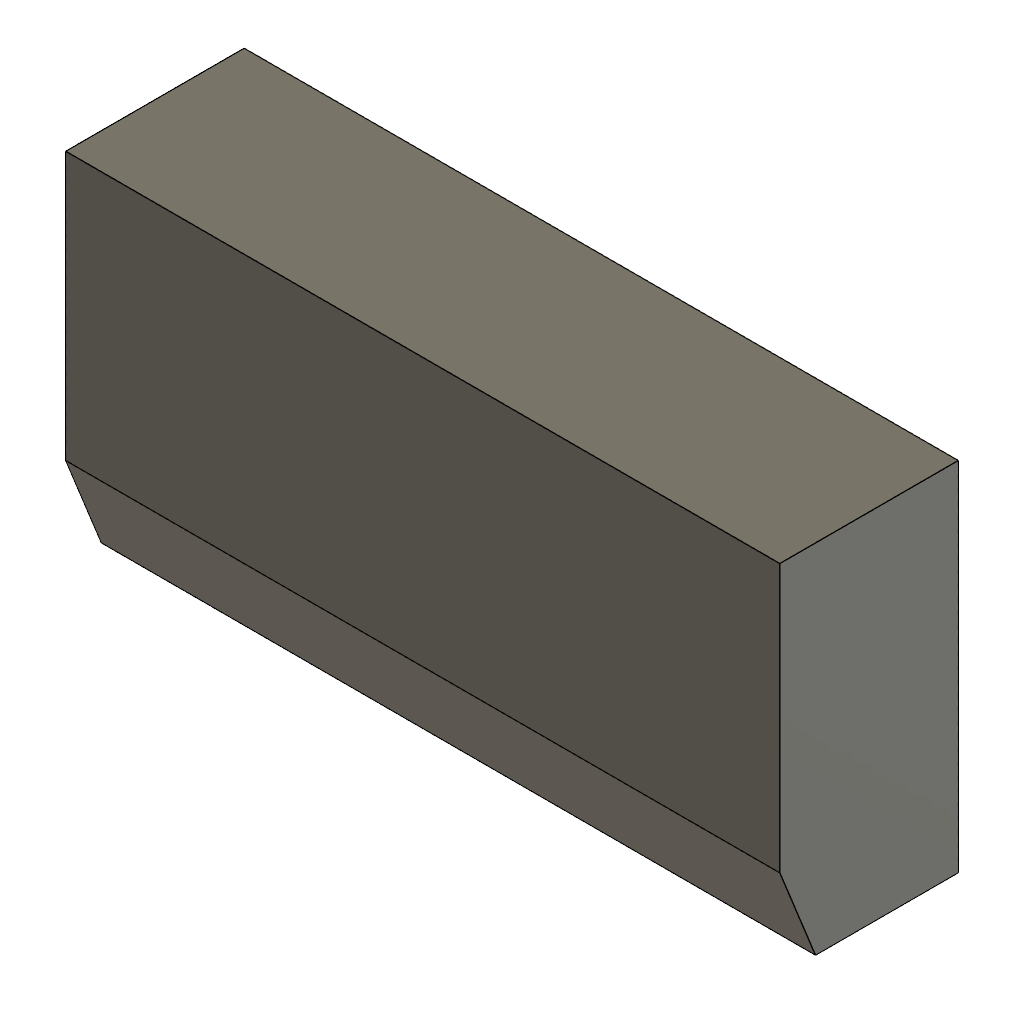
chamfer_two_distances_flipped (Autodesk Fusion 360 design; units mm, degrees)
part number: 2026-11-13-14-48-48-251
Autodesk Fusion 360 part; units mm, degrees
sketch "Sketch1" plane through (0, 0, 0) normal (0, 0, 1) x (1, 0, 0)
  line L0 (0, 0) -> (20, 0)
  line L1 (20, 0) -> (20, 10)
  line L2 (20, 10) -> (0, 10)
  line L3 (0, 10) -> (0, 0)
extrude "Extrude1" add sketch "Sketch1" along normal blind 5
chamfer "Chamfer1" distance 1 distance2 2.5 1 edges at (10, 0, 5) measured on face at (6.6667, 0, 1.6667) tangent chain off
